Autodesk Fusion 360 part; units mm, degrees
(part 3 of 3)
  spline S654 degree 3 poles (-39.6915, -35.6634) (-39.7868, -35.8777) (-39.7471, -35.9015) (-39.9693, -36.4175) knots 0 0 0 0 1 1 1 1
  spline S655 degree 3 poles (-39.9693, -36.4175) (-40.1916, -36.9334) (-40.8266, -38.259) (-41.0409, -38.759) knots 0 0 0 0 1 1 1 1
  spline S656 degree 3 poles (-41.0409, -38.759) (-41.2552, -39.2591) (-41.2076, -39.267) (-41.2393, -39.4337) knots 0 0 0 0 1 1 1 1
  spline S657 degree 3 poles (-41.2393, -39.4337) (-41.2711, -39.6004) (-41.2711, -39.6004) (-41.2393, -39.7512) knots 0 0 0 0 1 1 1 1
  spline S658 degree 3 poles (-41.2393, -39.7512) (-41.2076, -39.902) (-41.1361, -40.1878) (-41.0409, -40.3465) knots 0 0 0 0 1 1 1 1
  spline S659 degree 3 poles (-41.0409, -40.3465) (-40.9456, -40.5053) (-40.7869, -40.6164) (-40.6837, -40.7037) knots 0 0 0 0 1 1 1 1
  spline S660 degree 3 poles (-40.6837, -40.7037) (-40.5805, -40.791) (-40.5011, -40.8228) (-40.4059, -40.8625) knots 0 0 0 0 1 1 1 1
  spline S661 degree 3 poles (-40.4059, -40.8625) (-40.3106, -40.9022) (-40.2789, -40.926) (-40.1281, -40.9419) knots 0 0 0 0 1 1 1 1
  spline S662 degree 3 poles (-40.1281, -40.9419) (-39.9773, -40.9577) (-39.6518, -40.9577) (-39.4931, -40.9419) knots 0 0 0 0 1 1 1 1
  spline S663 degree 3 poles (-39.4931, -40.9419) (-39.3343, -40.926) (-40.5885, -41.434) (-39.1756, -40.8625) knots 0 0 0 0 1 1 1 1
  spline S664 degree 3 poles (-39.1756, -40.8625) (-37.7627, -40.291) (-32.4128, -38.0605) (-31.0396, -37.5287) knots 0 0 0 0 1 1 1 1
  spline S665 degree 3 poles (-31.0396, -37.5287) (-29.6665, -36.9969) (-30.9682, -36.4969) (-30.9206, -37.6875) knots 0 0 0 0 1 1 1 1
  spline S666 degree 3 poles (-30.9206, -37.6875) (-30.873, -38.8781) (-30.8253, -43.4184) (-30.7618, -44.6725) knots 0 0 0 0 1 1 1 1
  spline S667 degree 3 poles (-30.7618, -44.6725) (-30.6983, -45.9266) (-30.6586, -45.0694) (-30.5634, -45.2281) knots 0 0 0 0 1 1 1 1
  spline S668 degree 3 poles (-30.5634, -45.2281) (-30.4681, -45.3869) (-30.3491, -45.5218) (-30.2062, -45.625) knots 0 0 0 0 1 1 1 1
  spline S669 degree 3 poles (-30.2062, -45.625) (-30.0633, -45.7282) (-29.9046, -45.8155) (-29.73, -45.8631) knots 0 0 0 0 1 1 1 1
  spline S670 degree 3 poles (-29.73, -45.8631) (-29.5553, -45.9107) (-29.2855, -45.9107) (-29.1346, -45.9028) knots 0 0 0 0 1 1 1 1
  spline S671 degree 3 poles (-29.214, -45.2281) (-29.3093, -45.2519) (-29.4521, -45.244) (-29.5315, -45.2281) knots 0 0 0 0 1 1 1 1
  spline S672 degree 3 poles (-29.5315, -45.2281) (-29.6109, -45.2122) (-29.6268, -45.2043) (-29.6903, -45.1487) knots 0 0 0 0 1 1 1 1
  spline S673 degree 3 poles (-29.6903, -45.1487) (-29.7538, -45.0932) (-29.8649, -45.0297) (-29.9284, -44.9106) knots 0 0 0 0 1 1 1 1
  spline S674 degree 3 poles (-29.9284, -44.9106) (-29.9919, -44.7915) (-30.0395, -45.6726) (-30.0871, -44.4344) knots 0 0 0 0 1 1 1 1
  spline S675 degree 3 poles (-30.0871, -44.4344) (-30.1348, -43.1961) (-30.1745, -38.7194) (-30.2062, -37.489) knots 0 0 0 0 1 1 1 1
  spline S676 degree 3 poles (-30.2062, -37.489) (-30.238, -36.2587) (-30.2538, -37.1557) (-30.2856, -37.0525) knots 0 0 0 0 1 1 1 1
  spline S677 degree 3 poles (-30.2856, -37.0525) (-30.3173, -36.9493) (-30.3491, -36.9414) (-30.4046, -36.8937) knots 0 0 0 0 1 1 1 1
  spline S678 degree 3 poles (-30.4046, -36.8937) (-30.4602, -36.8461) (-30.4999, -36.7905) (-30.6031, -36.7747) knots 0 0 0 0 1 1 1 1
  spline S679 degree 3 poles (-30.6031, -36.7747) (-30.7063, -36.7588) (-30.5634, -36.6) (-31.0396, -36.7747) knots 0 0 0 0 1 1 1 1
  spline S680 degree 3 poles (-31.0396, -36.7747) (-31.5159, -36.9493) (-32.0477, -37.2271) (-33.4606, -37.8065) knots 0 0 0 0 1 1 1 1
  spline S681 degree 3 poles (-33.4606, -37.8065) (-34.8735, -38.386) (-38.4295, -39.8544) (-39.5328, -40.2672) knots 0 0 0 0 1 1 1 1
  spline S682 degree 3 poles (-39.5328, -40.2672) (-40.6361, -40.6799) (-39.9455, -40.3148) (-40.0884, -40.2672) knots 0 0 0 0 1 1 1 1
  spline S683 degree 3 poles (-40.0884, -40.2672) (-40.2313, -40.2195) (-40.3424, -40.0608) (-40.4059, -39.9894) knots 0 0 0 0 1 1 1 1
  spline S684 degree 3 poles (-40.4059, -39.9894) (-40.4694, -39.9179) (-40.4614, -39.9179) (-40.4853, -39.8306) knots 0 0 0 0 1 1 1 1
  spline S685 degree 3 poles (-40.4853, -39.8306) (-40.5091, -39.7433) (-40.5408, -39.6163) (-40.525, -39.4734) knots 0 0 0 0 1 1 1 1
  spline S686 degree 3 poles (-40.525, -39.4734) (-40.5091, -39.3305) (-41.1044, -40.6482) (-40.3662, -38.9575) knots 0 0 0 0 1 1 1 1
  spline S687 degree 3 poles (-40.3662, -38.9575) (-39.628, -37.2668) (-36.8023, -30.9962) (-36.08, -29.3531) knots 0 0 0 0 1 1 1 1
  spline S688 degree 3 poles (-36.08, -29.3531) (-35.3576, -27.71) (-36.0323, -29.1944) (-36.0403, -29.115) knots 0 0 0 0 1 1 1 1
  spline S689 degree 3 poles (-36.0403, -29.115) (-36.0482, -29.0356) (-36.08, -28.9404) (-36.1196, -28.8769) knots 0 0 0 0 1 1 1 1
  spline S690 degree 3 poles (-36.1196, -28.8769) (-36.1593, -28.8134) (-36.1911, -28.7657) (-36.2784, -28.7181) knots 0 0 0 0 1 1 1 1
  spline S691 degree 3 poles (-36.2784, -28.7181) (-36.3657, -28.6705) (-35.3973, -28.6625) (-36.6356, -28.599) knots 0 0 0 0 1 1 1 1
  spline S692 degree 3 poles (-36.6356, -28.599) (-37.8738, -28.5355) (-42.4458, -28.4244) (-43.7, -28.3609) knots 0 0 0 0 1 1 1 1
  spline S693 degree 3 poles (-43.7, -28.3609) (-44.9541, -28.2974) (-44.0651, -28.2974) (-44.1762, -28.2419) knots 0 0 0 0 1 1 1 1
  spline S694 degree 3 poles (-44.1762, -28.2419) (-44.2873, -28.1863) (-44.327, -28.1069) (-44.3746, -28.0434) knots 0 0 0 0 1 1 1 1
  spline S695 degree 3 poles (-44.3746, -28.0434) (-44.4223, -27.9799) (-44.4461, -27.9323) (-44.454, -27.845) knots 0 0 0 0 1 1 1 1
  spline S696 degree 3 poles (-44.454, -27.845) (-44.462, -27.7577) (-44.5096, -27.6704) (-44.4143, -27.5275) knots 0 0 0 0 1 1 1 1
  spline S697 degree 3 poles (-44.4143, -27.5275) (-44.3191, -27.3846) (-45.7161, -28.5117) (-43.8984, -26.9719) knots 0 0 0 0 1 1 1 1
  spline S698 degree 3 poles (-43.8984, -26.9719) (-42.0807, -25.432) (-35.2862, -19.7567) (-33.5003, -18.2803) knots 0 0 0 0 1 1 1 1
  spline S699 degree 3 poles (-33.5003, -18.2803) (-31.7143, -16.8039) (-33.286, -18.1454) (-33.1828, -18.1215) knots 0 0 0 0 1 1 1 1
  spline S700 degree 3 poles (-33.1828, -18.1215) (-33.0796, -18.0977) (-33.0002, -18.0977) (-32.905, -18.1215) knots 0 0 0 0 1 1 1 1
  spline S701 degree 3 poles (-32.905, -18.1215) (-32.8097, -18.1454) (-33.6987, -17.2325) (-32.5875, -18.2803) knots 0 0 0 0 1 1 1 1
  spline S702 degree 3 poles (-32.5875, -18.2803) (-31.4762, -19.328) (-27.9123, -22.8444) (-26.2375, -24.4319) knots 0 0 0 0 1 1 1 1
  spline S703 degree 3 poles (-26.2375, -24.4319) (-24.5626, -26.0194) (-23.7292, -26.7575) (-22.5465, -27.8053) knots 0 0 0 0 1 1 1 1
  spline S704 degree 3 poles (-22.5465, -27.8053) (-21.3638, -28.853) (-19.7446, -30.1707) (-19.1334, -30.7025) knots 0 0 0 0 1 1 1 1
  spline S705 degree 3 poles (-19.1334, -30.7025) (-18.5222, -31.2343) (-18.9191, -30.9009) (-18.8556, -30.9803) knots 0 0 0 0 1 1 1 1
  spline S706 degree 3 poles (-18.8556, -30.9803) (-18.7921, -31.0597) (-18.7921, -31.0914) (-18.7762, -31.1787) knots 0 0 0 0 1 1 1 1
  spline S707 degree 3 poles (-18.7762, -31.1787) (-18.7603, -31.266) (-18.7365, -31.3692) (-18.7762, -31.4962) knots 0 0 0 0 1 1 1 1
  spline S708 degree 3 poles (-18.7762, -31.4962) (-18.8159, -31.6232) (-18.038, -30.6231) (-19.0143, -31.9328) knots 0 0 0 0 1 1 1 1
  spline S709 degree 3 poles (-19.0143, -31.9328) (-19.9906, -33.2425) (-23.0307, -37.1954) (-24.65, -39.3544) knots 0 0 0 0 1 1 1 1
  spline S710 degree 3 poles (-24.65, -39.3544) (-26.2692, -41.5134) (-28.0155, -43.9105) (-28.7378, -44.8709) knots 0 0 0 0 1 1 1 1
  spline S711 degree 3 poles (-28.7378, -44.8709) (-29.4601, -45.8314) (-28.8965, -45.0455) (-28.9759, -45.109) knots 0 0 0 0 1 1 1 1
  spline S712 degree 3 poles (-28.9759, -45.109) (-29.0553, -45.1725) (-29.1188, -45.2043) (-29.214, -45.2281) knots 0 0 0 0 1 1 1 1
extrude "Extrude120" cut sketch "Sketch104" against normal blind 0.5 contours S455 S456 S457 S458 S459 S460 S461 S462 S463 S464 S465 S466 S467 S468 S469 S470 S471 S472 S473 S474 S475 S476 S477 S478 S479 S480 S481 S482 S483 S484 S485 S486 S487 S488 S489 S490 S491 S492 S493 S494 S495 S496 S497 S498 S499 S500 S501 S502 S503 S504 S505 S506 S507 S508 S509 S510 S511 S512 S513 S514 S515 S516 S517 S518 S519 S520 S521 S522 S523 S524 S525 S526 S527 S528 S529 S530 S531 S532 S533 S534 S535 S536 S537 S538 S539 S540 S541 S542 S543 S544 S545 S546 S547 S548 S549 S550 S551 S552 S553 S554 S555 S556 S557 S558 S559 S560 S561 S562 S563 S564 S565 S566 S567 S568 S569 S570 S571 S572 S573 S574 S575 S576 S577 S578 S579 S580 S581 S582 S583 S584 S585 S586 S587 S588 S589 S590 S591 S592 S593 S594 S595 S596 S597 S598 S599 S600 S601 S602 S603 S604 S605 S606 S607 | S699 S700 S701 | S671 S672 S673 S674 S675 S676 S677 S678 S679 S680 S681 S682 S683 S684 S685 S686 S687 S688 S689 S690 S691 S692 S693 S694 S695 S696 S697 S698 S699 S701 S702 S703 S704 S705 S706 S707 S708 S709 S710 S711 S712 bodies 1
delete_face "DeleteFace31" 8 faces at (49.3778, -41.207, 14.0085) (-13.8167, -48.4409, 13.8201) (49.4409, -13.4833, 13.8201) (46.0695, 46.9372, 14.0085) (-47.71, -45.3729, 14.0085) (13.8167, 46.6401, 15.6209) (-49.3778, 41.207, 14.0085) (-49.4409, 13.4833, 13.8201) on bodies 2
sketch "Sketch105" plane through (0, 0, 15.63) normal (0, 0, 1) x (-1, 0, 0)
  line L0 (49.45, -40.45) -> (49.45, 40.45)
  arc A0 (49.45, 40.45) -> (41.45, 48.45) centre (41.45, 40.45) ccw
  line L1 (41.45, 48.45) -> (-41.45, 48.45)
  arc A1 (-41.45, 48.45) -> (-49.45, 40.45) centre (-41.45, 40.45) ccw
  line L2 (-49.45, 40.45) -> (-49.45, -40.45)
  arc A2 (-49.45, -40.45) -> (-41.45, -48.45) centre (-41.45, -40.45) ccw
  line L3 (-41.45, -48.45) -> (41.45, -48.45)
  arc A3 (41.45, -48.45) -> (49.45, -40.45) centre (41.45, -40.45) ccw
  line L4 (-3.4481, -11.55) -> (24.9519, -11.55)
  line L5 (24.9519, -11.55) -> (24.9519, -24.95)
  line L6 (24.9519, -24.95) -> (-3.4481, -24.95)
  line L7 (-3.4481, -24.95) -> (-3.4481, -11.55)
  line L8 (27.77, -9.9) -> (-27.56, -9.9)
  arc A4 (-29.56, -7.9) -> (-27.56, -9.9) centre (-27.56, -7.9) ccw
  line L9 (-29.56, -7.9) -> (-29.56, 28.5)
  arc A5 (-27.56, 30.5) -> (-29.56, 28.5) centre (-27.56, 28.5) ccw
  line L10 (-27.56, 30.5) -> (27.77, 30.5)
  arc A6 (29.77, 28.5) -> (27.77, 30.5) centre (27.77, 28.5) ccw
  line L11 (29.77, 28.5) -> (29.77, -7.9)
  arc A7 (27.77, -9.9) -> (29.77, -7.9) centre (27.77, -7.9) ccw
  circle A8 centre (-19.7639, -16.9931) radius 4.6
  circle A9 centre (-35.7497, 34.7499) radius 1.7
  circle A10 centre (35.7567, -34.7538) radius 1.7
  circle A11 centre (35.7575, 34.7473) radius 1.7
  circle A12 centre (-35.7482, -34.7503) radius 1.7
  line L12 (42.45, -35.45) -> (42.45, 35.45)
  line L13 (36.45, 41.45) -> (-36.45, 41.45)
  line L14 (-42.45, 35.45) -> (-42.45, -35.45)
  line L15 (-36.45, -41.45) -> (36.45, -41.45)
  arc A13 (42.45, 35.45) -> (36.45, 41.45) centre (36.45, 35.45) ccw
  arc A14 (-36.45, 41.45) -> (-42.45, 35.45) centre (-36.45, 35.45) ccw
  arc A15 (-42.45, -35.45) -> (-36.45, -41.45) centre (-36.45, -35.45) ccw
  arc A16 (36.45, -41.45) -> (42.45, -35.45) centre (36.45, -35.45) ccw
  dimension "d585" = 7
  dimension "d586" = 7
  dimension "d587" = 7
  dimension "d588" = 7
  dimension "d589" = 6
  constraint tangent L12 A13
  constraint tangent L13 A13
  constraint tangent L14 A14
  constraint tangent L13 A14
  constraint equal A13 A14
  constraint tangent L14 A15
  constraint tangent L15 A15
  constraint equal A13 A15
  constraint tangent L15 A16
  constraint tangent L12 A16
  constraint equal A13 A16
  measures "d585" distance of L0 L12
  measures "d586" distance of L1 L13
  measures "d587" distance of L2 L14
  measures "d588" distance of L3 L15
  measures "d589" radius of A13
extrude "Extrude121" add sketch "Sketch105" along normal blind 3 contours L0 A0 L1 A1 L2 A2 L3 A3 bodies 2
delete_face "DeleteFace32" 8 faces at (47.71, -45.3729, -1.3785) (13.8167, -48.1025, -2.1266) (49.1025, 13.4833, -2.1266) (-49.3778, -41.207, -1.3785) (49.3778, 41.207, -1.3785) (-43.3276, 48.1894, -1.3785) (-13.8167, 48.1025, -2.1266) (-49.1821, -13.4833, -2) on bodies 1
fillet "Fillet32" radius 2 16 edges at (49.45, 0, -3) (47.1069, -46.1069, -3) (0, -48.45, -3) (-47.1069, -46.1069, -3) (-49.45, 0, -3) (-47.1069, 46.1069, -3) (0, 48.45, -3) (47.1069, 46.1069, -3) (49.45, 0, 18.63) (47.1069, 46.1069, 18.63) (0, 48.45, 18.63) (-47.1069, 46.1069, 18.63) (-49.45, 0, 18.63) (-47.1069, -46.1069, 18.63) (0, -48.45, 18.63) (47.1069, -46.1069, 18.63) on bodies 1 2
fillet "Fillet33" radius 1.5 8 edges at (0, 41.45, 18.63) (40.6926, 39.6926, 18.63) (42.45, 0, 18.63) (40.6926, -39.6926, 18.63) (0, -41.45, 18.63) (-40.6926, -39.6926, 18.63) (-42.45, 0, 18.63) (-40.6926, 39.6926, 18.63) on bodies 2
named bodies: "Bottom-Plate", "Top- plate"
